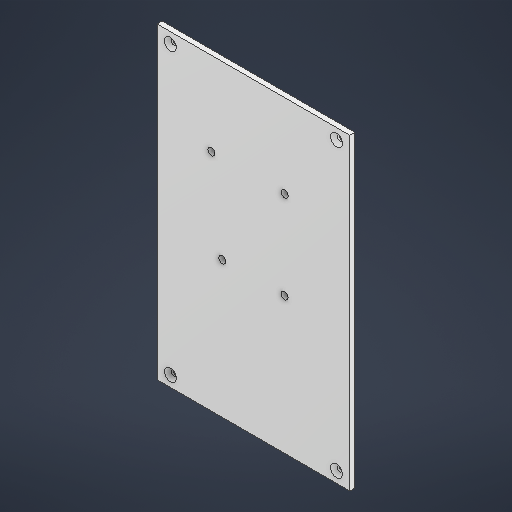
# Autodesk Inventor part: Крышка_задняя
Saved by Autodesk Inventor 2026 (Build 300175050, 175E)
## iProperties
Created: 2026-10-30
Part Number: Крышка_задняя
Material: Пластик АБС
Document SubType Name: Modeling
Designer: VK7
Density: 1.06 g/cm^3
Appearance: Гладкий — белый
Author: VK7
Autodesk Inventor part; units mm, degrees
ref_plane "YZ Plane" through (0, 0, 0) normal (1, 0, 0) x (0, 1, 0)
ref_plane "XZ Plane" through (0, 0, 0) normal (0, 1, 0) x (-1, 0, 0)
ref_plane "XY Plane" through (0, 0, 0) normal (0, 0, 1) x (1, 0, 0)
sketch "Эскиз1" plane through (0, 0, 0) normal (0, 0, 1) x (1, 0, 0)
  line L0 (0, 0) -> (113.8, 0)
  line L1 (113.8, 0) -> (113.8, 181.8)
  line L2 (113.8, 181.8) -> (0, 181.8)
  line L3 (0, 181.8) -> (0, 0)
  dimension "d0" = 113.8
  dimension "d1" = 181.8
  constraints: 8 end point, 2 parallel, 1 horizontal, 1 perpendicular
  measures "d0" distance of L2.end L1.end
  measures "d1" distance of L1.end L0.end
extrude "Выдавливание1" add sketch "Эскиз1" along normal blind 3
sketch "Эскиз2" plane through (0, 0, 3) normal (0, 0, 1) x (1, 0, 0)
  line L0 (0, 181.8) -> (0, 0) projected
  line L1 (0, 90.9) -> (113.8, 90.9)
  line L2 (113.8, 0) -> (113.8, 181.8) projected
  line L3 (-0.1, 181.9) -> (113.9, 181.9)
  line L4 (113.9, 181.9) -> (113.9, -0.1)
  line L5 (113.9, -0.1) -> (-0.1, -0.1)
  line L6 (-0.1, -0.1) -> (-0.1, 181.9)
  line L7 (-0.1, 181.9) -> (113.9, -0.1) construction
  line L8 (113.9, 181.9) -> (-0.1, -0.1) construction
  line L9 (-0.1, 181.8) -> (7.9, 181.8)
  line L10 (113.8, 181.8) -> (0, 181.8) projected
  line L11 (7.9, 181.9) -> (7.9, 175.4)
  circle A0 centre (7.9, 175.4) radius 1.55
  line L12 (56.9, 181.8) -> (56.9, 176.8)
  circle A1 centre (105.9, 175.4) radius 1.55
  circle A2 centre (7.9, 6.4) radius 1.55
  circle A3 centre (105.9, 6.4) radius 1.55
  point P0 (56.9, 90.9)
  dimension "d4" = 114
  dimension "d5" = 182
  dimension "d6" = 8
  dimension "d7" = 6.5
  dimension "d8" = 3.1
  dimension "d9" = 5
  constraints: 20 end point, 6 midpoint, 4 centre point, 3 perpendicular, 3 point on line, 3 symmetric about line, 2 parallel, 1 coincident, 1 horizontal, 3 other
  measures "d4" distance of L4.end L5.end
  measures "d5" distance of L3.end L4.end
  measures "d6" distance of L9.start L9.end
  measures "d7" distance of L11.start L11.end
  measures "d8" diameter of A0
  measures "d9" distance of L12.start L12.end
extrude "Выдавливание2" cut sketch "Эскиз2" against normal blind 3 contours A0 | A1 | A2 | A3
chamfer "Фаска1" distance 2 angle 45 4 edges at (6.35, 175.4, 3) (104.35, 175.4, 3) (6.35, 6.4, 3) (104.35, 6.4, 3)
sketch "Эскиз3" plane through (0, 0, 0) normal (0, 0, -1) x (-1, 0, 0)
  line L0 (-113.8, 181.8) -> (0, 181.8) projected
  line L1 (-56.9, 181.8) -> (-14.6652, 181.8)
  line L2 (-56.9, 181.8) -> (-38.5, 181.8)
  line L3 (-38.5, 181.8) -> (-38.5, 176.6)
  line L4 (-56.9, 181.8) -> (-56.9, 178.7)
  line L5 (-38.5, 176.6) -> (-38.5, 124.6)
  line L6 (-38.5, 124.6) -> (-81.7, 124.6)
  line L7 (-38.5, 176.6) -> (-38.5, 126.1)
  line L8 (-38.5, 176.6) -> (12, 176.6) construction
  line L9 (-38.5, 126.1) -> (-25.4485, 126.1)
  circle A0 centre (-38.5, 75.6) radius 2.1
  circle A1 centre (-75.3, 75.6) radius 2.1
  circle A2 centre (-32.1, 127.6) radius 2.1
  circle A3 centre (-75.3, 127.6) radius 2.1
  point P0 (0, 0)
  dimension "d15" = 18.4
  dimension "d16" = 5.2
  dimension "d18" = 52
  dimension "d20" = 43.2
  dimension "d24" = 50.5
  dimension "d25" = 90
  constraints: 18 end point, 4 centre point, 3 perpendicular, 2 coincident, 2 horizontal, 2 point on line, 2 vertical, 1 collinear, 1 midpoint, 1 symmetric about line
  measures "d15" distance of L1.start L2.end
  measures "d16" distance of L2.end L3.end
  measures "d18" distance of L5.start L5.end
  measures "d20" distance of L6.start L6.end
  measures "d24" distance of L5.start L7.end
  measures "d25" angle of L7 L8
extrude "Выдавливание4" cut sketch "Эскиз3" against normal blind 10
move faces "Перенос1" translate (0, 5, 0) faces at (30.7719, 129.2267, 2) (75.3846, 129.6983, 2) (73.6212, 76.8616, 2) (36.8212, 76.8616, 2)
